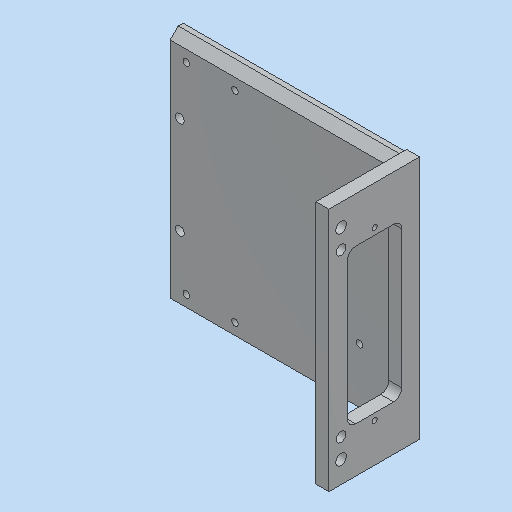
# Autodesk Inventor part: MM0948AN100_G01_132
Saved by Autodesk Inventor 2023.3 (Build 273359000, 359)
## iProperties
RuleStatus: InUse
Created: 2023-03-23
Part Number: MM0948AN100_G01_132
Material: 3.3206 AlMgSi0,5 - AW 6060
Description: =<RBPARTNOTITLE2>
Document SubType Name: Modeling
Designer: FH/Wi
Mass: 540.393 g
Surface Area: 592.94 cm^2
Volume: 200.145 cm^3
Density: 2.7 g/cm^3
Appearance: Aluminium AnP
Vendor: --
AnP_Kategorie: 1
AnP_Material: =<Material>
MaxAbmaße: 154 x 56 x 146 (FM)
AnP_TemplVers: 20200821
RBDOCUMENTTYPE: DRF
RBDOCUMENTVERSION: 00
RBDRAWINGMAINSCALE: 1:1
RBDRAWINGMISSINGSPEC: --
RBDRAWINGVOLUME: --
RBDSV1: 0850
RBGBEDGESIN1: +0,5
RBGBEDGESIN2: +0,2
RBGBEDGESOUT1: -0,3
RBGBEDGESOUT2: -0,1
RBMATERIAL: =<Material>
RBMATMEETS: --
RBMATNO: =<Part Number>
RBPARTMADEOF: L 56 x 136 x 8 x 154 (FM)
RBPARTNO: SIEHE MNR
RBPARTNOTITLE1: manufactured part
RBPARTNOTITLE2: Anfertigungsteil
RBPARTSAFETYINDICATOR: --
RBSURFACE: anodised colourless
RBSURFACE2: eloxiert farblos
RBZEDGESNORM: ISO13715:2002-06
RBZGENDIMCLASS: m
RBZGENDIMNORM: ISO 2768-1:1989-11
RBZGENGEOCLASS: H
RBZGENGEONORM: ISO 2768-2:1989-11
RBZSURFACENORM: ISO13D2:2002-02
RBZTOLERANCENORM: ISO 14405-1:2010-12
AnP_Kommentar_aktuell: =<Comments>
AnP_Material_aktuell: =<Material>
Author: FH/Wi
Keywords: =<RBPARTMADEOF>
Comments: =<RBSURFACE2>
Revision Number: 01
Autodesk Inventor part; units mm, degrees
ref_plane "YZ Plane" through (0, 0, 0) normal (1, 0, 0) x (0, 1, 0)
ref_plane "XZ Plane" through (0, 0, 0) normal (0, 1, 0) x (-1, 0, 0)
ref_plane "XY Plane" through (0, 0, 0) normal (0, 0, 1) x (1, 0, 0)
sketch "Skizze1" plane through (0, 0, 0) normal (0, 0, 1) x (1, 0, 0)
  line L0 (0, 0) -> (-8, 0)
  line L1 (-8, 0) -> (-8, 48)
  line L2 (-8, 48) -> (-146, 48)
  line L3 (-146, 48) -> (-146, 56)
  line L4 (-146, 56) -> (0, 56)
  line L5 (0, 56) -> (0, 0)
  dimension "d0" = 8
  dimension "d1" = 146
  dimension "d2" = 8
  dimension "d3" = 56
  constraints: 12 end point, 5 perpendicular, 1 horizontal
  measures "d0" distance of L2.end L3.end
  measures "d1" distance of L3.end L4.end
  measures "d2" distance of L0.start L0.end
  measures "d3" distance of L4.end L0.start
extrude "Extrusion1" add sketch "Skizze1" along normal mid plane 151
sketch "Skizze3" plane through (-146, 48, 75.5) normal (-1, 0, 0) x (0, 0, 1)
  line L0 (-149.5, 0) -> (-151, 0)
  line L1 (-151, 0) -> (-151, 8)
  line L2 (-151, 8) -> (-149.5, 8)
  line L3 (-149.5, 8) -> (-149.5, 0)
  line L4 (-151, 0) -> (0, 0) construction
  line L5 (-1.5, 8) -> (0, 8)
  line L6 (0, 8) -> (0, 0)
  line L7 (0, 0) -> (-1.5, 0)
  line L8 (-1.5, 0) -> (-1.5, 8)
  point P0 (-75.5, -48)
  dimension "d15" = 148
  constraints: 16 end point, 4 parallel, 2 coincident, 2 horizontal, 2 perpendicular, 2 point on line, 1 collinear
  measures "d15" distance between parallel lines of L8 L3
extrude "Extrusion3" cut sketch "Skizze3" against normal up to surface (138 mm away)
chamfer "Fase2" distance 5 angle 45 2 edges at (-77, 48, -74) (-77, 48, 74)
sketch "Skizze4" plane through (-146, 48, 69) normal (0, -1, 0) x (1, 0, 0)
  line L0 (0, -138) -> (0, 0) projected
  line L1 (10, -7) -> (40, -7)
  line L2 (40, -7) -> (40, -131)
  line L3 (40, -131) -> (10, -131)
  line L4 (10, -131) -> (10, -7)
  line L5 (138, 5) -> (0, 5) projected
  point P0 (146, -69)
  point P1 (0, -69)
  point P2 (10, -69)
  dimension "d25" = 10
  dimension "d55" = 12
  dimension "d56" = 30
  dimension "d67" = 124
  constraints: 8 end point, 3 coincident, 2 midpoint, 2 parallel, 1 horizontal, 1 horizontal alignment, 1 perpendicular
  measures "d25" distance from line of L1.start L0
  measures "d55" distance between parallel lines of L1 L5
  measures "d56" distance of L1.start L1.end
  measures "d67" distance of L1.end L2.end
hole "Bohrung1" at (-136, 48, 62) at (-136, 48, -62) at (-106, 48, -62) at (-106, 48, 62) direction (0, 1, 0) diameter 4.134 end through all thread size "M5x0.8" designation "M5" class "6H" standard "ISO Metric profile"
sketch "Skizze5" plane through (-146, 56, 74) normal (0, 1, 0) x (1, 0, 0)
  line L0 (146, -1.5) -> (146, 149.5) projected
  line L1 (146, 74) -> (98.4845, 74)
  point P0 (117, 109)
  point P1 (117, 39)
  dimension "d35" = 29
  dimension "d36" = 70
  constraints: 2 end point, 1 horizontal, 1 symmetric about line
  measures "d35" distance from line of L0 point (117, 109)
  measures "d36" distance of point (117, 39) point (117, 109)
hole "Bohrung2" at (-29, 56, -35) at (-29, 56, 35) direction (0, -1, 0) diameter 4.134 end through all thread size "M5x0.8" designation "M5" class "6H" standard "ISO Metric profile"
sketch "Skizze6" plane through (-8, 0, -75.5) normal (-1, 0, 0) x (0, 0, 1)
  line L0 (0, 0) -> (151, 0) projected
  line L1 (75.5, 0) -> (75.5, 18.3604)
  line L2 (0, 0) -> (0, 56) projected
  point P0 (13.5, 7.5)
  point P1 (137.5, 7.5)
  dimension "d44" = 7.5
  dimension "d54" = 124
  dimension "d84" = 62
  constraints: 2 end point, 1 symmetric about line, 1 vertical
  measures "d44" distance from line of L0 point (13.5, 7.5)
  measures "d54" distance of point (137.5, 7.5) point (13.5, 7.5)
  measures "d84" distance from line of L1 point (13.5, 7.5)
hole "Bohrung3" at (-8, 7.5, -62) at (-8, 7.5, 62) direction (1, 0, 0) diameter 6.6 end through all clearance for "Inbusschraube ISO 4762  versenkt" size "M6" standard "ISO"
sketch "Skizze7" plane through (-8, 0, -75.5) normal (-1, 0, 0) x (0, 0, 1)
  line L0 (25.5, 7.5) -> (125.5, 7.5)
  line L1 (125.5, 7.5) -> (137.5, 7.5)
  line L2 (25.5, 7.5) -> (13.5, 7.5)
  circle A0 centre (13.5, 7.5) radius 3.3 projected
  circle A1 centre (137.5, 7.5) radius 3.3 projected
  point P0 (75.5, 0)
  dimension "d53" = 12
  constraints: 6 end point, 2 coincident, 2 horizontal, 1 collinear
  measures "d53" distance of L0.start L2.end
hole "Bohrung4" at (-8, 7.5, -50) at (-8, 7.5, 50) direction (1, 0, 0) diameter 6 end through all
sketch "Skizze8" plane through (-146, 48, 69) normal (0, -1, 0) x (1, 0, 0)
  line L0 (0, -69) -> (29.7759, -69)
  line L1 (0, -138) -> (0, 0) projected
  point P0 (146, -69)
  point P1 (6, -39)
  point P2 (6, -99)
  dimension "d64" = 6
  dimension "d65" = 60
  constraints: 2 end point, 1 horizontal, 1 midpoint, 1 symmetric about line
  measures "d64" distance from line of point (6, -39) L1
  measures "d65" distance of point (6, -99) point (6, -39)
hole "Bohrung5" at (-140, 48, 30) at (-140, 48, -30) direction (0, 1, 0) diameter 5.5 end through all clearance for "Inbusschraube ISO 4762  versenkt" size "M5" standard "ISO"
sketch "Skizze9" plane through (0, 0, 75.5) normal (1, 0, 0) x (0, 0, -1)
  line L0 (28, 45) -> (123, 45)
  line L1 (123, 45) -> (123, 11.5)
  line L2 (123, 11.5) -> (28, 11.5)
  line L3 (28, 11.5) -> (28, 45)
  line L4 (75.5, -11.2) -> (75.5, 67.2) projected
  line L5 (151, 0) -> (0, 0) projected
  point P0 (75.5, 0)
  dimension "d68" = 11.5
  dimension "d70" = 45
  dimension "d71" = 95
  constraints: 8 end point, 2 parallel, 1 horizontal, 1 perpendicular, 1 other
  measures "d68" distance between parallel lines of L5 L2
  measures "d70" distance between parallel lines of L5 L0
  measures "d71" distance of L1.end L2.end
extrude "Extrusion4" cut sketch "Skizze9" against normal through all
fillet "Rundung1" radius 5 4 edges at (-4, 45, 47.5) (-4, 11.5, 47.5) (-4, 11.5, -47.5) (-4, 45, -47.5)
sketch "Skizze10" plane through (0, 0, 75.5) normal (1, 0, 0) x (0, 0, -1)
  line L0 (28, 16.5) -> (28, 40) projected
  line L1 (123, 40) -> (123, 16.5) projected
  line L2 (28, 28.25) -> (123, 28.25) construction
  point P0 (75.5, 0)
  point P1 (24, 28.25)
  point P2 (127, 28.25)
  dimension "d75" = 4
  dimension "d76" = 4
  constraints: 2 end point, 2 midpoint, 2 point on line
  measures "d75" distance from line of L0 point (24, 28.25)
  measures "d76" distance from line of L1 point (127, 28.25)
hole "Bohrung6" at (0, 28.25, 51.5) at (0, 28.25, -51.5) direction (-1, 0, 0) diameter 3.242 end through all thread size "M4x0.7" designation "M4" class "6H" standard "ISO Metric profile"
equation "\"d76\" = d75"
